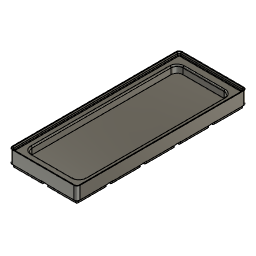
gridfintity_pinecil_case_holder (Autodesk Fusion 360 design; units mm, degrees)
Autodesk Fusion 360 part; units mm, degrees
note: some values were not read from the file. Set by a fixed rule: which face or edge a step refers to.
sketch "Sketch1" plane through (0, 0, 0) normal (0, 0, 1) x (1, 0, 0) in component "Blank Storage"
  line L0 (0, 42) -> (42, 42)
  line L1 (42, 42) -> (42, 0)
  line L2 (42, 0) -> (0, 0)
  line L3 (0, 0) -> (0, 42)
  line L4 (0, 42) -> (42, 0) construction
  line L5 (42, 21) -> (0, 21) construction
  line L6 (42, 14.5) -> (0, 14.5)
  line L7 (42, 27.5) -> (0, 27.5)
  line L8 (27.5, 42) -> (27.5, 0)
  line L9 (14.5, 42) -> (14.5, 0)
  line L10 (14.5, 14.5) -> (0, 0) construction
  circle A0 centre (8, 8) radius 1.5
  circle A1 centre (34, 8) radius 1.5
  circle A2 centre (34, 34) radius 1.5
  circle A3 centre (8, 34) radius 1.5
  circle A4 centre (8, 8) radius 3.25
  circle A5 centre (34, 8) radius 3.25
  circle A6 centre (34, 34) radius 3.25
  circle A7 centre (8, 34) radius 3.25
  point P0 (21, 21)
  dimension "d1" = 42
  dimension "d2" = 42
  dimension "d65" = 13
  dimension "d67" = 90
  dimension "d69" = 3
  dimension "d71" = 360
  dimension "d80" = 6.5
  dimension "d85" = 8
  constraint horizontal L0
  constraint perpendicular L0 L1
  constraint parallel L0 L2
  constraint parallel L1 L3
  constraint coincident L2.end L3.start
  constraint midpoint L1 L5.start
  constraint midpoint L3 L5.end
  constraint coincident L1 L6.start
  constraint coincident L3 L6.end
  constraint perpendicular L3 L6
  constraint symmetric L5 L6.start L7.start
  constraint symmetric L5 L6.end L7.end
  constraint midpoint L4 P0
  constraint coincident L9 L10.start
  constraint coincident L6 L10.start
  constraint concentric A0 A4
  constraint coincident L10 A0.centre
  measures "d1" distance of L1.end L2.end
  measures "d2" distance of L0.end L1.end
  measures "d65" distance of L6 L7
  measures "d69" diameter of A0
  measures "d80" diameter of A4
  measures "d85" distance of L2 A0.centre
extrude "Extrude1" add sketch "Sketch1" along normal blind 5 contours L0 L3 L7 L9 | L0 L7 L8 L9 | L3 L6 L7 L9 | L0 L1 L7 L8 | L6 L7 L8 L9 | L2 L3 L6 L9 | L1 L6 L7 L8 | L2 L6 L8 L9 | L1 L2 L6 L8 | A0 | A1 | A2 | A3 | A4 | A5 | A6 | A7 makes body 1 in component "Blank Storage"
ref_plane "WorkPlane1" through (21, 21, 2.5) normal (0, -1, 0) x (1, 0, 0) in component "Blank Storage"
sketch "Sketch2" plane through (0, 21, 0) normal (0, -1, 0) x (1, 0, 0) in component "Blank Storage"
  line L0 (42, 0) -> (0, 0)
  line L1 (0, 0) -> (0, 5)
  line L2 (3.2, 0) -> (2.4, 0.8)
  line L3 (3.2, 0) -> (0, 0) construction
  line L4 (2.4, 0.8) -> (2.4, 2.6)
  line L5 (2.4, 2.6) -> (0, 5)
  line L6 (0, 5) -> (-5.1222, 5)
  line L7 (-5.1222, 5) -> (-5.1222, -0.0937)
  line L8 (-5.1222, -0.0937) -> (0, 0)
  dimension "d39" = 45
  dimension "d40" = 45
  dimension "d41" = 0.8
  dimension "d43" = 5
  dimension "d112" = 2.4
  constraint horizontal L3
  constraint coincident L0 L2.start
  constraint perpendicular L0 L4
  constraint coincident L1 L5.end
  constraint coincident L0.end L1.start
  constraint coincident L1.end L5.end
  constraint perpendicular L1 L6
  constraint perpendicular L6 L7
  measures "d39" angle of L2 L3
  measures "d40" angle of L4 L5
  measures "d41" distance of L2.end L3
  measures "d43" distance of L3 L1.end
  measures "d112" distance of L0.end L2.end
sketch "Sketch3" plane through (0, 0, 0) normal (0, 0, -1) x (1, 0, 0)
  line L0 (42, 0) -> (0, 0)
  line L1 (0, 0) -> (0, -42)
  line L2 (0, -42) -> (42, -42)
  line L3 (42, -42) -> (42, 0)
  arc A0 (4, 0) -> (0, -4) centre (4, -4) ccw
  line L4 (0, -42) -> (42, 0) construction
  arc A1 (0, -38) -> (4, -42) centre (4, -38) ccw
  arc A2 (38, -42) -> (42, -38) centre (38, -38) ccw
  arc A3 (42, -4) -> (38, 0) centre (38, -4) ccw
  line L5 (0, -4) -> (0, -38)
  line L6 (4, -42) -> (38, -42)
  line L7 (42, -38) -> (42, -4)
  line L8 (38, 0) -> (4, 0)
  point P0 (21, -21)
  dimension "d37" = 360
  constraint coincident L1.end L2.start
  constraint coincident L0.start L3.end
  constraint midpoint L4 P0
sweep "Sweep1" cut profiles "Sketch2" path "Sketch3" along L8 A0 L5 A1 L6 A2 L7 A3 section 1 bodies 1 in component "Blank Storage"
extrude "Extrude1'" add sketch "Sketch3" against normal up to surface (5 mm away) separate body makes body 2 in component "Blank Frame"
combine "Combine1" operation cut target body 2 tool bodies 1 keep tools in component "Blank Frame"
move_face "OffsetFaces1" offset -0.25 24 faces at (40.4, 26.6667, 3.4) (40.6565, 38.2324, 3.6667) (39.1041, 39.158, 2) (15.3333, 39.0667, 0.2667) (39.2397, 38.1085, 0.4444) (26.6667, 39.6, 1.4) (26.6667, 40.4, 3.4) (39.6, 15.3333, 1.4) (39.0667, 15.3333, 0.2667) (38.2324, 1.3435, 3.6667) (3.7676, 40.6565, 3.6667) (3.9239, 39.5982, 1.4) (3.8915, 39.2397, 0.4444) (2.4, 26.6667, 1.4) (2.9333, 15.3333, 0.2667) (1.6, 26.6667, 3.4) (1.3435, 3.7676, 3.6667) (2.4018, 3.9239, 1.4) (2.7603, 3.8915, 0.4444) (15.3333, 2.4, 1.4) (15.3333, 2.9333, 0.2667) (15.3333, 0.8, 4.2) (39.2397, 3.8915, 0.4444) (39.158, 2.8959, 1.4) on bodies 2 in component "Blank Frame"
pattern_linear "R-Pattern1" count 2 spacing 42 along (1, 0, 0) count 5 spacing 42 along (0, 1, 0) of bodies 1 makes body 3 at (67.3333, 15.3333, 5) makes body 4 at (15.3333, 70, 5) makes body 5 at (67.3333, 57.3333, 5) makes body 6 at (15.3333, 112, 5) makes body 7 at (67.3333, 99.3333, 5) makes body 8 at (16.6667, 141.3333, 5) makes body 9 at (56, 141.3333, 5) makes body 10 at (15.3333, 182, 5) makes body 11 at (56, 183.3333, 5) in component "Blank Storage"
sketch "Sketch4" plane through (0, 0, 5) normal (0, 0, 1) x (-1, 0, 0) in component "Blank Storage"
  line L0 (-4, 0) -> (-80, 0)
  line L1 (-84, -4) -> (-84, -206)
  line L2 (-80, -210) -> (-4, -210)
  line L3 (0, -206) -> (0, -4)
  arc A0 (0, -4) -> (-4, 0) centre (-4, -4) ccw
  arc A1 (-80, 0) -> (-84, -4) centre (-80, -4) ccw
  arc A2 (-84, -206) -> (-80, -210) centre (-80, -206) ccw
  arc A3 (-4, -210) -> (0, -206) centre (-4, -206) ccw
  line L4 (-0.25, -206) -> (-0.25, -4)
  arc A4 (-0.25, -4) -> (-4, -0.25) centre (-4, -4) ccw
  line L5 (-4, -0.25) -> (-80, -0.25)
  arc A5 (-80, -0.25) -> (-83.75, -4) centre (-80, -4) ccw
  line L6 (-83.75, -4) -> (-83.75, -206)
  arc A6 (-83.75, -206) -> (-80, -209.75) centre (-80, -206) ccw
  line L7 (-80, -209.75) -> (-4, -209.75)
  arc A7 (-4, -209.75) -> (-0.25, -206) centre (-4, -206) ccw
  point P0 (-84, 0)
  point P1 (0, -210)
  dimension "d44" = 84
  dimension "d45" = 210
  dimension "d48" = 4
  dimension "d49" = 4
  dimension "d50" = 4
  dimension "d51" = 4
  dimension "d138" = -0.25
  constraint horizontal L0
  constraint vertical L1
  constraint horizontal L2
  constraint vertical L3
  constraint coincident origin L0
  constraint coincident origin L3
  constraint tangent L0 A0
  constraint tangent L3 A0
  constraint coincident P0 L0
  constraint coincident P0 L1
  constraint tangent L0 A1
  constraint tangent L1 A1
  constraint tangent L1 A2
  constraint tangent L2 A2
  constraint coincident P1 L2
  constraint coincident P1 L3
  constraint tangent L2 A3
  constraint tangent L3 A3
  measures "d44" distance of origin P0
  measures "d45" distance of origin P1
  measures "d48" radius of A0
  measures "d49" radius of A1
  measures "d50" radius of A2
  measures "d51" radius of A3
extrude "Extrude2" add sketch "Sketch4" along normal blind 11.8 contours L0 L1 L2 L3 A0 A1 A2 A3 | L4 A4 L5 A5 L6 A6 L7 A7 bodies 3 10 11 6 7 8 9 4 5 1 in component "Blank Storage"
sketch "Sketch5" plane through (21, 21, 2.5) normal (0, -1, 0) x (1, 0, 0) in component "Blank Storage"
  line L0 (-18.6, 0.1) -> (-21, 2.5)
  line L1 (59, 2.5) -> (-17, 2.5)
  line L2 (-18.6, -1.7) -> (-18.6, 0.1)
  line L3 (-17.8, -2.5) -> (-18.6, -1.7)
  line L4 (-17, 14.3) -> (-21, 14.3)
  line L5 (-17, 14.3) -> (-21, 14.3)
  line L6 (-17, 14.3) -> (59, 14.3)
  line L7 (63, 14.3) -> (59, 14.3)
  line L8 (63, 14.3) -> (59, 14.3)
  line L9 (59, 14.3) -> (-17, 14.3)
  line L10 (-18.6, 16.9) -> (-21, 19.3)
  line L11 (-18.6, 15.1) -> (-18.6, 16.9)
  line L12 (-17.8, 14.3) -> (-18.6, 15.1)
  line L13 (-21, 2.5) -> (-21, 14.3)
  line L14 (-21, 14.3) -> (-21, 2.5)
  line L15 (-17.8, 14.3) -> (-21, 14.3)
  line L16 (-21, 19.3) -> (-21, 14.3)
  line L17 (-17.9768, 14.1232) -> (-18.85, 14.9964)
  line L18 (-18.85, 14.9964) -> (-18.85, 16.7964)
  line L19 (-18.85, 16.7964) -> (-21.1768, 19.1232)
  dimension "d54" = 0
  dimension "d55" = 16.8
  constraint coincident L14 L4.end
  constraint perpendicular L14 L15
sweep "Sweep2" add profiles "Sketch5" along 8 edges at (84, 105, 16.8) (82.8284, 208.8284, 16.8) (42, 210, 16.8) (1.1716, 208.8284, 16.8) (0, 105, 16.8) (1.1716, 1.1716, 16.8) (42, 0, 16.8) (82.8284, 1.1716, 16.8) section 1 contours L4 L5 L15 L16 L17 L18 L19 on bodies 3 bodies 3 in component "Blank Storage"
fillet "Fillet2" radius 0.6 8 edges at (82.8284, 1.1716, 21.4464) (84, 105, 21.4464) (82.8284, 208.8284, 21.4464) (42, 210, 21.4464) (1.1716, 208.8284, 21.4464) (0, 105, 21.4464) (1.1716, 1.1716, 21.4464) (42, 0, 21.4464) on bodies 3 in component "Blank Storage"
pattern_linear "R-Pattern1'" count 2 spacing 42 along (1, 0, 0) count 5 spacing 42 along (0, 1, 0) of bodies 2 makes body 12 at (57.3333, 0.7167, 0) makes body 13 at (41.2833, 57.3333, 0) makes body 14 at (83.2833, 57.3333, 0) makes body 15 at (15.3333, 84.7167, 0) makes body 16 at (57.3333, 84.7167, 0) makes body 17 at (15.3333, 126.7167, 0) makes body 18 at (57.3333, 126.7167, 0) makes body 19 at (15.3333, 168.7167, 0) makes body 20 at (57.3333, 168.7167, 0) in component "Blank Frame"
sketch "Sketch1 (2)" plane through (0, 0, 0) normal (0, 0, 1) x (1, 0, 0) in component "Blank Frame"
  line L0 (0, 0) -> (4, 0)
  line L1 (0, 0) -> (0, 4)
  arc A0 (0, 4) -> (4, 0) centre (4, 4) ccw
  line L2 (0, 0) -> (42, 0) construction
  line L3 (42, 0) -> (42, 105) construction
  line L4 (84, 0) -> (80, 0)
  line L5 (84, 0) -> (84, 4)
  arc A1 (80, 0) -> (84, 4) centre (80, 4) ccw
  line L6 (42, 105) -> (0, 105) construction
  line L7 (0, 105) -> (0, 0) construction
  line L8 (0, 210) -> (4, 210)
  line L9 (0, 210) -> (0, 206)
  arc A2 (4, 210) -> (0, 206) centre (4, 206) ccw
  line L10 (84, 210) -> (84, 206)
  line L11 (84, 210) -> (80, 210)
  arc A3 (84, 206) -> (80, 210) centre (80, 206) ccw
  dimension "d113" = 4
  dimension "d114" = 4
  dimension "d115" = 42
  dimension "d116" = 105
  constraint coincident L0.start L1.start
  constraint horizontal L0
  constraint perpendicular L0 L1
  constraint tangent L0 A0
  constraint perpendicular L1 L2
  constraint perpendicular L2 L3
  constraint symmetric L0.start L3 L4.start
  constraint symmetric L0.end L3 L4.end
  constraint symmetric L1.end L3 L5.end
  constraint symmetric A0 L3 A1
  constraint perpendicular L3 L6
  constraint vertical L7
  constraint symmetric L0.start L6 L8.start
  constraint symmetric L0.end L6 L8.end
  constraint symmetric L1.end L6 L9.end
  constraint symmetric A0 L6 A2
  constraint symmetric L4.start L6 L10.start
  constraint symmetric L4.end L6 L11.end
  constraint symmetric L5.end L6 L10.end
  constraint symmetric A1 L6 A3
  measures "d113" distance of L0.start L0.end
  measures "d114" distance of L0.start L1.end
  measures "d115" distance of L0.start L2.end
  measures "d116" distance of L2.end L3.end
extrude "Extrude2'" cut sketch "Sketch1 (2)" along normal through all bodies 18 13 14 15 16 17 12 in component "Blank Frame"
ref_plane "WorkPlane1" through (42, 105, 13.2232) normal (1, 0, 0) x (0, 1, 0) in component "Blank Storage"
extrude "Extrude5" cut sketch "Sketch4" along normal through all and the other way through all bodies 3 in component "Blank Storage"
sketch "Sketch7" plane through (0, 0, 16.8) normal (0, 0, 1) x (-1, 0, 0)
  arc A0 (-4, -207.1536) -> (-2.8464, -206) centre (-4, -206) ccw
  line L0 (-2.8464, -206) -> (-2.8464, -4)
  arc A1 (-2.8464, -4) -> (-4, -2.8464) centre (-4, -4) ccw
  line L1 (-4, -2.8464) -> (-80, -2.8464)
  arc A2 (-80, -2.8464) -> (-81.1536, -4) centre (-80, -4) ccw
  line L2 (-81.1536, -4) -> (-81.1536, -206)
  arc A3 (-81.1536, -206) -> (-80, -207.1536) centre (-80, -206) ccw
  line L3 (-80, -207.1536) -> (-4, -207.1536)
  line L4 (-42, -207.1536) -> (-42, -2.8464) construction
  line L5 (-2.8464, -105) -> (-81.1536, -105) construction
  line L6 (-67.35, -198.15) -> (-16.65, -198.15)
  line L7 (-9.25, -190.75) -> (-9.25, -19.25)
  line L8 (-16.65, -11.85) -> (-67.35, -11.85)
  line L9 (-74.75, -19.25) -> (-74.75, -190.75)
  line L10 (-74.75, -198.15) -> (-9.25, -11.85) construction
  line L11 (-9.25, -198.15) -> (-74.75, -11.85) construction
  arc A4 (-16.65, -198.15) -> (-9.25, -190.75) centre (-16.65, -190.75) ccw
  arc A5 (-9.25, -19.25) -> (-16.65, -11.85) centre (-16.65, -19.25) ccw
  arc A6 (-67.35, -11.85) -> (-74.75, -19.25) centre (-67.35, -19.25) ccw
  arc A7 (-74.75, -190.75) -> (-67.35, -198.15) centre (-67.35, -190.75) ccw
  point P0 (-42, -105)
  dimension "d190" = 65.5
  dimension "d191" = 186.3
  dimension "d192" = 7.4
  constraint midpoint L3 L4.start
  constraint midpoint L1 L4.end
  constraint midpoint L0 L5.start
  constraint midpoint L2 L5.end
  constraint horizontal L6
  constraint perpendicular L6 L7
  constraint parallel L6 L8
  constraint parallel L7 L9
  constraint coincident L10 P0
  constraint coincident L11 P0
  constraint midpoint L5 P0
  constraint coincident L11.start L6
  constraint coincident L11.start L7
  constraint tangent L6 A4
  constraint tangent L7 A4
  constraint coincident L10.end L7
  constraint coincident L10.end L8
  constraint tangent L7 A5
  constraint tangent L8 A5
  constraint equal A4 A5
  constraint coincident L11.end L8
  constraint coincident L11.end L9
  constraint tangent L8 A6
  constraint tangent L9 A6
  constraint equal A4 A6
  constraint coincident L10.start L9
  constraint coincident L10.start L6
  constraint tangent L9 A7
  constraint tangent L6 A7
  constraint equal A4 A7
  measures "d190" distance of L10.start L11.start
  measures "d191" distance of L10.start L11.end
  measures "d192" radius of A4
extrude "Extrude11" cut sketch "Sketch7" against normal up to surface (8.8 mm away) contours L6 L7 L8 L9 A4 A5 A6 A7 bodies 3 in component "Blank Storage"
fillet "Fillet11" radius 1.5 8 edges at (42, 198.15, 16.8) (72.5826, 195.9826, 16.8) (74.75, 105, 16.8) (72.5826, 14.0174, 16.8) (42, 11.85, 16.8) (11.4174, 14.0174, 16.8) (9.25, 105, 16.8) (11.4174, 195.9826, 16.8) on bodies 3 in component "Blank Storage"
component "Blank Storage" placed x (1, 0, 0) y (0, 1, 0) z (0, 0, 1) at (0, 0, 0)
component "Blank Frame" placed x (1, 0, 0) y (0, 1, 0) z (0, 0, 1) at (0, 0, 0)
equation "d1 = slotDimension"
equation "d2 = slotDimension"
equation "d3 = nestingDepth"
equation "slotDimension = 42 mm"
equation "nestingDepth = 5 mm"
equation "nestingRimWidth = 2.4 mm"
equation "nestingClearance = 0.25 mm"
equation "cornerFillet = 4 mm"
equation "d33 = slotDimension"
equation "d34 = slotDimension"
equation "d38 = -slotDimension / 2"
equation "d43 = nestingDepth"
equation "d44 = slotDimension * slotsWide"
equation "d45 = slotDimension * slotsDeep"
equation "d46 = slotDimension * slotsHigh - nestingDepth"
equation "d48 = cornerFillet"
equation "d49 = cornerFillet"
equation "d50 = cornerFillet"
equation "d51 = cornerFillet"
equation "d55 = slotDimension * slotsHigh"
equation "ledStripWidth = 13 mm"
equation "ledSlotHeight = 4 mm"
equation "d65 = ledStripWidth"
equation "screwTightDiameter = 3 mm"
equation "d69 = screwTightDiameter"
equation "magnetDiameter = 6.5 mm"
equation "magnetThiccness = 2.4 mm"
equation "d80 = magnetDiameter"
equation "d93 = slotDimension"
equation "d94 = slotDimension"
equation "wallThiccness = 1.2 mm"
equation "d112 = nestingRimWidth"
equation "d113 = cornerFillet"
equation "d114 = cornerFillet"
equation "d115 = slotDimension * slotsWide / 2"
equation "d116 = slotDimension * slotsDeep / 2"
equation "d118 = -slotsWide / 2 * slotDimension"
equation "tolerance_loose = 0.5 mm"
equation "d190 = 65 mm + tolerance_loose"
equation "d191 = 185.8 mm + tolerance_loose"
